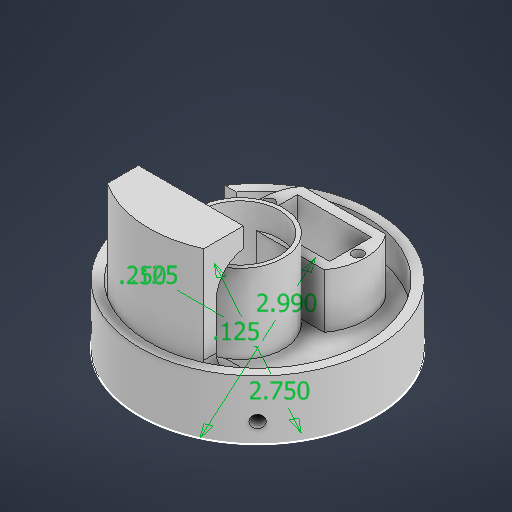
# Autodesk Inventor part: Parachute Bulkhead_V2_1
Saved by Autodesk Inventor 2027 (Build 310192060, 192F)
## iProperties
Created: 2026-10-03
Part Number: Parachute Bulkhead_V2_1
Material: Generic
Document SubType Name: Modeling
Designer: troop
Density: 1 g/cm^3
Appearance: Default
Author: troop
Autodesk Inventor part; units mm, degrees
ref_plane "YZ Plane" through (0, 0, 0) normal (1, 0, 0) x (0, 1, 0)
ref_plane "XZ Plane" through (0, 0, 0) normal (0, 1, 0) x (-1, 0, 0)
ref_plane "XY Plane" through (0, 0, 0) normal (0, 0, 1) x (1, 0, 0)
sketch "Sketch1" plane through (0, 0, 0) normal (0, 1, 0) x (-1, 0, 0)
  circle A0 centre (0, 0) radius 37.973
  line L0 (34.798, 3.175) -> (37.973, 3.175)
  line L1 (37.973, 3.175) -> (37.973, -3.175)
  line L2 (37.973, -3.175) -> (34.798, -3.175)
  line L3 (34.798, -3.175) -> (34.798, 3.175)
  circle A1 centre (0, 0) radius 34.925
  point P0 (37.973, 0)
  point P1 (37.84, 3.175)
  point P2 (37.84, -3.175)
  point P3 (34.798, 2.9757)
  point P4 (34.798, -2.9757)
  dimension "d0" = 75.946
  dimension "d1" = 6.35
  dimension "d2" = 3.175
  dimension "d3" = 3.175
  dimension "d6" = 69.85
  constraints: 8 end point, 2 coincident, 2 parallel, 1 centre point, 1 horizontal, 1 midpoint, 1 perpendicular, 3 other
  measures "d1" distance of L0.end L1.end
  measures "d2" distance of L1.end L2.end
  measures "d3" distance from line of point (0, 0) L2
  measures "d6" diameter of A1
extrude "Extrusion2" add sketch "Sketch1" along normal blind 9.525 contours L3 A1 picked at (-0.0606, -10.2216)
extrude "Extrusion3" add sketch "Sketch1" along normal blind 19.05 contours L0 L3 A1 L2 A0 picked at (-35.5397, 4.1423)
ref_plane "Work Plane2" through (-37.84, 0, 3.175) normal (-0.7071068, 0, -0.7071068) x (0, 1, 0)
sketch "Sketch2" plane through (-37.84, 0, 3.175) normal (-0.7071068, 0, -0.7071068) x (0, 1, 0)
  circle A0 centre (6.35, 29.002) radius 1.9939
  line L0 (0, -8.971) -> (0, 66.975) projected
  line L1 (19.05, -8.971) -> (19.05, 66.975) projected
  point P0 (0, 29.002)
  point P1 (0, 0)
  point P2 (0, 4.4901)
  point P3 (19.05, 0)
  point P4 (19.05, 4.4901)
  point P5 (0, 29.002)
  dimension "d12" = 3.9878
  dimension "d14" = 12.7
  dimension "d15" = 0
  constraints: 1 centre point, 1 midpoint
  measures "d12" diameter of A0
  measures "d14" distance from line of L1 A0.centre
  measures "d15" vertical distance of point (0, 29.002) A0.centre
extrude "Extrusion4" cut sketch "Sketch2" along normal mid plane 152.4
ref_plane "Work Plane3" through (-37.84, 0, -3.175) normal (-0.7071068, 0, 0.7071068) x (0, 1, 0)
sketch "Sketch3" plane through (-37.84, 0, -3.175) normal (-0.7071068, 0, 0.7071068) x (0, 1, 0)
  circle A0 centre (6.35, -29.002) radius 1.9939
  line L0 (19.05, -66.975) -> (19.05, 8.971) projected
  point P0 (0, -29.002)
  point P1 (19.05, -4.4901)
  point P2 (19.05, 0)
  dimension "d19" = 3.9878
  dimension "d20" = 0
  dimension "d21" = 12.7
  constraints: 1 centre point
  measures "d19" diameter of A0
  measures "d20" vertical distance of point (0, -29.002) A0.centre
  measures "d21" distance from line of L0 A0.centre
extrude "Extrusion5" cut sketch "Sketch3" along normal mid plane 152.4
sketch "Sketch4" plane through (0, 9.525, 0) normal (0, 1, 0) x (1, 0, 0)
  line L0 (14.4145, 22.225) -> (-9.398, 22.225)
  line L1 (-9.398, 22.225) -> (-9.398, 8.7312)
  line L2 (-9.398, 8.7312) -> (14.4145, 8.7313)
  line L3 (14.4145, 8.7313) -> (14.4145, 22.225)
  arc A0 (-34.798, -2.9757) -> (-34.798, 2.9757) centre (0, 0) ccw projected
  line L4 (-34.798, 2.9757) -> (-34.798, -2.9757) projected
  line L5 (15.9024, 5.5562) -> (-10.8859, 5.5562)
  line L6 (20.0805, 28.575) -> (20.7645, 28.575)
  line L7 (20.7645, 28.575) -> (20.7645, 28.0819)
  line L8 (15.9024, 25.4) -> (-10.8859, 25.4)
  arc A1 (15.9024, 5.5562) -> (15.9024, 25.4) centre (2.5083, 15.4781) ccw
  arc A2 (-10.8859, 25.4) -> (-10.8859, 5.5562) centre (2.5083, 15.4781) ccw
  point P0 (-34.798, 0)
  point P1 (-9.398, 15.4781)
  dimension "d24" = 23.8125
  dimension "d25" = 13.4938
  dimension "d26" = 12.7
  dimension "d27" = 25.4
  dimension "d28" = 3.175
  dimension "d37" = 3.175
  dimension "d38" = 2.5082
  dimension "d39" = 15.4781
  dimension "d40" = 16.6687
  dimension "d41" = 16.6687
  constraints: 16 end point, 6 point on circle, 3 parallel, 2 centre point, 2 horizontal, 2 midpoint, 1 perpendicular
  measures "d24" distance of L2.end L1.end
  measures "d25" distance of L0.end L1.end
  measures "d26" distance edge to line of A0 L0
  measures "d27" horizontal distance of point (-34.798, 0) point (-9.398, 15.478)
  measures "d28" distance between parallel lines of L2 L5
  measures "d37" distance between parallel lines of L8 L0
  measures "d38" horizontal distance of point (0, 0) A1.centre
  measures "d39" vertical distance of A1.centre point (0, 0)
  measures "d40" radius of A1
  measures "d41" radius of A2
extrude "Extrusion6" add sketch "Sketch4" along normal blind 17.4625 contours L5 A2 L8 A1
sketch "Sketch5" plane through (-9.398, 9.525, -8.7312) normal (1, 0, 0) x (0, 0, -1)
  line L0 (26.1937, 0) -> (-43.6562, 0) projected
  line L1 (12.3, 7.62) -> (1.1875, 7.62)
  line L2 (1.1875, 7.62) -> (1.1875, 0)
  line L3 (1.1875, 0) -> (12.3, 0)
  line L4 (12.3, 0) -> (12.3, 7.62)
  line L5 (0, 0) -> (0, 17.4625) projected
  point P0 (-8.7313, -9.525)
  point P1 (-11.707, 0)
  point P2 (-5.7555, 0)
  point P3 (12.3, 0)
  dimension "d42" = 11.1125
  dimension "d43" = 1.1874
  dimension "d44" = 7.62
  constraints: 8 end point, 2 parallel, 1 horizontal, 1 perpendicular, 1 point on line
  measures "d42" distance of L1.start L1.end
  measures "d43" distance between parallel lines of L5 L2
  measures "d44" distance of L3.end L1.start
extrude "Extrusion7" cut sketch "Sketch5" against normal blind 17.4625
sketch "Sketch6" plane through (0, 26.9875, 0) normal (0, 1, 0) x (1, 0, 0)
  circle A0 centre (-11.7856, 15.4781) radius 1.75
  circle A1 centre (16.8021, 15.4781) radius 1.75
  line L0 (14.4145, 8.7313) -> (-9.398, 8.7312) projected
  arc A2 (-10.8859, 25.4) -> (-10.8859, 5.5563) centre (2.5083, 15.4781) ccw projected
  line L1 (-9.398, 8.7312) -> (-9.398, 22.225) projected
  line L2 (14.4145, 22.225) -> (14.4145, 8.7313) projected
  point P0 (0, 0)
  point P1 (-14.1605, 15.4781)
  point P2 (-9.398, 15.4781)
  dimension "d47" = 3.5
  dimension "d48" = 3.5
  dimension "d49" = 6.7469
  dimension "d50" = 4.7625
  dimension "d51" = 2.3876
  dimension "d52" = 2.3876
  constraints: 2 centre point, 1 horizontal alignment, 1 midpoint, 1 point on circle
  measures "d47" diameter of A0
  measures "d48" diameter of A1
  measures "d49" distance from line of A0.centre L0
  measures "d50" distance of point (-14.16, 15.478) point (-9.398, 15.478)
  measures "d51" distance from line of L1 A0.centre
  measures "d52" distance from line of L2 A1.centre
extrude "Extrusion8" cut sketch "Sketch6" against normal blind 5
sketch "Sketch7" plane through (0, 9.525, 0) normal (0, 1, 0) x (1, 0, 0)
  line L0 (-26.6646, 9.9187) -> (-41.1244, 9.9187)
  line L1 (-41.1244, 9.9187) -> (-41.1244, 21.0312)
  line L2 (-41.1244, 21.0312) -> (-26.6646, 21.0312)
  line L3 (-26.6646, 21.0312) -> (-26.6646, 9.9187)
  line L4 (-9.398, 9.9187) -> (-13.2061, 9.9187) projected
  line L5 (-9.398, 21.0312) -> (-13.2083, 21.0312) projected
  point P0 (0, 0)
  dimension "d55" = 0
  dimension "d57" = 11.1125
  constraints: 8 end point, 2 parallel, 1 horizontal, 1 perpendicular
  measures "d55" distance between parallel lines of L2 L5
  measures "d57" distance of L0.end L1.end
extrude "Extrusion9" cut sketch "Sketch7" along normal mid plane 152.4
extrude "Extrusion10" add sketch "Sketch1" along normal blind 19.05 contours A0 L2 L3 A1 L0 | A1 L3 picked at (36.9521, -0.3531) picked at (34.8215, 0.6617)
sketch "Sketch8" plane through (0, 9.525, 0) normal (0, 1, 0) x (1, 0, 0)
  line L0 (14.4272, -27.7812) -> (-19.3508, -27.7812)
  line L1 (-19.3508, -27.7812) -> (-19.3508, -32.3609)
  line L2 (-19.3508, -32.3609) -> (14.4272, -32.3609)
  line L3 (14.4272, -32.3609) -> (14.4272, -27.7812)
  line L4 (-10.8859, 5.5563) -> (15.9024, 5.5562) projected
  line L5 (14.4145, 22.225) -> (14.4145, 8.7313) projected
  arc A0 (-34.798, -2.9757) -> (-27.8827, 21.0312) centre (0, 0) ccw projected
  arc A1 (-13.135, -32.3609) -> (13.135, -32.3609) centre (0, 0) ccw
  point P0 (14.4272, -31.8058)
  point P1 (-19.3508, -29.0741)
  dimension "d62" = 33.3375
  dimension "d63" = 14.4272
  dimension "d64" = 33.778
  dimension "d65" = 32.3609
  constraints: 8 end point, 4 point on circle, 2 parallel, 2 point on line, 1 centre point, 1 horizontal, 1 perpendicular
  measures "d62" distance between parallel lines of L0 L4
  measures "d63" distance from line of point (0, 0) L3
  measures "d64" distance of L1.end L2.end
  measures "d65" vertical distance of point (0, 0) L1.end
extrude "Extrusion11" add sketch "Sketch8" along normal blind 41.275 contours L3 A0 L2 L1 L0 | A0 L2
fillet "Fillet1" radius 10.16 3 edges at (-2.4618, 9.525, 27.7812) (14.4272, 9.525, 29.7935) (-19.3508, 9.525, 28.4277)
sketch "Sketch9" plane through (0, 50.8, 0) normal (0, 1, 0) x (1, 0, 0)
  line L0 (-19.3508, -27.7812) -> (14.4272, -27.7812) projected
  line L1 (14.4272, -27.7812) -> (-19.3508, -27.7812)
  line L2 (-19.3508, -27.7812) -> (-19.3508, -19.05)
  line L3 (-19.3508, -19.05) -> (14.4272, -19.05)
  line L4 (14.4272, -19.05) -> (14.4272, -27.7812)
  arc A0 (-19.3508, -29.0741) -> (14.4272, -31.8058) centre (0, 0) ccw projected
  point P0 (0, -34.925)
  dimension "d69" = 0
  dimension "d70" = 15.875
  constraints: 8 end point, 2 parallel, 1 horizontal, 1 perpendicular, 1 point on circle
  measures "d69" horizontal distance of point (0, 0) point (0, -34.925)
  measures "d70" distance from line of L3 point (0, -34.925)
extrude "Extrusion12" add sketch "Sketch9" against normal blind 6.35
fillet "Fillet2" radius 10.16 1 edges at (-2.4618, 44.45, 27.7812)
sketch "Sketch10" plane through (0, 9.525, 0) normal (0, 1, 0) x (1, 0, 0)
  line L0 (-10.8859, 5.5563) -> (15.9024, 5.5562) projected
  circle A0 centre (0, -5.5563) radius 11.7475
  circle A1 centre (0, -5.5563) radius 10.4775
  point P0 (0, 0)
  point P1 (-3.81, 5.5562)
  point P2 (3.81, 5.5562)
  dimension "d75" = 0
  dimension "d78" = 5.5563
  dimension "d79" = 23.495
  dimension "d80" = 20.955
  constraints: 2 centre point
  measures "d75" horizontal distance of point (0, 0) A0.centre
  measures "d78" distance of point (0, 0) A0.centre
  measures "d79" diameter of A0
  measures "d80" diameter of A1
extrude "Extrusion14" cut sketch "Sketch10" along normal mid plane 1.905
fillet "Fillet3" radius 0.635 1 edges at (-11.7475, 8.5725, 5.5563)
fillet "Fillet4" radius 0.635 1 edges at (-10.4775, 8.5725, 5.5563)
fillet "Fillet5" radius 0.635 1 edges at (0, 10.4775, -5.5562)
sketch "Sketch11" plane through (0, 9.525, 0) normal (0, 1, 0) x (1, 0, 0)
  circle A0 centre (0, -5.6719) radius 12.7
  circle A1 centre (0, -5.6719) radius 13.97
  point P0 (0, 0)
  dimension "d90" = 25.4
  dimension "d91" = 27.94
  constraints: 2 centre point, 1 coincident
  measures "d90" diameter of A0
  measures "d91" diameter of A1
extrude "Extrusion16" add sketch "Sketch11" along normal blind 25.4
body "Solid2"
